Autodesk Fusion 360 part; units mm, degrees
(part 4 of 8)
sketch "Servo ear rail | adjustable, purchased fit pending | profile" plane through (0, 0, 2.8) normal (0, 0, 1) x (1, 0, 0) in component "05 | MG996R gripper cassette"
  line L0 (10, -13) -> (16.5, -13)
  line L1 (16.5, -13) -> (17, -12.5)
  line L2 (17, -12.5) -> (17, 12.5)
  line L3 (17, 12.5) -> (16.5, 13)
  line L4 (16.5, 13) -> (10, 13)
  line L5 (10, 13) -> (9.5, 12.5)
  line L6 (9.5, 12.5) -> (9.5, -12.5)
  line L7 (9.5, -12.5) -> (10, -13)
  line L8 (11, -5) -> (11.0288, -5.2926)
  line L9 (11.0288, -5.2926) -> (11.1142, -5.574)
  line L10 (11.1142, -5.574) -> (11.2528, -5.8334)
  line L11 (11.2528, -5.8334) -> (11.4393, -6.0607)
  line L12 (11.4393, -6.0607) -> (11.6666, -6.2472)
  line L13 (11.6666, -6.2472) -> (11.926, -6.3858)
  line L14 (11.926, -6.3858) -> (12.2074, -6.4712)
  line L15 (12.2074, -6.4712) -> (12.5, -6.5)
  line L16 (12.5, -6.5) -> (15, -6.5)
  line L17 (15, -6.5) -> (15.2926, -6.4712)
  line L18 (15.2926, -6.4712) -> (15.574, -6.3858)
  line L19 (15.574, -6.3858) -> (15.8334, -6.2472)
  line L20 (15.8334, -6.2472) -> (16.0607, -6.0607)
  line L21 (16.0607, -6.0607) -> (16.2472, -5.8334)
  line L22 (16.2472, -5.8334) -> (16.3858, -5.574)
  line L23 (16.3858, -5.574) -> (16.4712, -5.2926)
  line L24 (16.4712, -5.2926) -> (16.5, -5)
  line L25 (16.5, -5) -> (16.4712, -4.7074)
  line L26 (16.4712, -4.7074) -> (16.3858, -4.426)
  line L27 (16.3858, -4.426) -> (16.2472, -4.1666)
  line L28 (16.2472, -4.1666) -> (16.0607, -3.9393)
  line L29 (16.0607, -3.9393) -> (15.8334, -3.7528)
  line L30 (15.8334, -3.7528) -> (15.574, -3.6142)
  line L31 (15.574, -3.6142) -> (15.2926, -3.5288)
  line L32 (15.2926, -3.5288) -> (15, -3.5)
  line L33 (15, -3.5) -> (12.5, -3.5)
  line L34 (12.5, -3.5) -> (12.2074, -3.5288)
  line L35 (12.2074, -3.5288) -> (11.926, -3.6142)
  line L36 (11.926, -3.6142) -> (11.6666, -3.7528)
  line L37 (11.6666, -3.7528) -> (11.4393, -3.9393)
  line L38 (11.4393, -3.9393) -> (11.2528, -4.1666)
  line L39 (11.2528, -4.1666) -> (11.1142, -4.426)
  line L40 (11.1142, -4.426) -> (11.0288, -4.7074)
  line L41 (11.0288, -4.7074) -> (11, -5)
  line L42 (11, 5) -> (11.0288, 4.7074)
  line L43 (11.0288, 4.7074) -> (11.1142, 4.426)
  line L44 (11.1142, 4.426) -> (11.2528, 4.1666)
  line L45 (11.2528, 4.1666) -> (11.4393, 3.9393)
  line L46 (11.4393, 3.9393) -> (11.6666, 3.7528)
  line L47 (11.6666, 3.7528) -> (11.926, 3.6142)
  line L48 (11.926, 3.6142) -> (12.2074, 3.5288)
  line L49 (12.2074, 3.5288) -> (12.5, 3.5)
  line L50 (12.5, 3.5) -> (15, 3.5)
  line L51 (15, 3.5) -> (15.2926, 3.5288)
  line L52 (15.2926, 3.5288) -> (15.574, 3.6142)
  line L53 (15.574, 3.6142) -> (15.8334, 3.7528)
  line L54 (15.8334, 3.7528) -> (16.0607, 3.9393)
  line L55 (16.0607, 3.9393) -> (16.2472, 4.1666)
  line L56 (16.2472, 4.1666) -> (16.3858, 4.426)
  line L57 (16.3858, 4.426) -> (16.4712, 4.7074)
  line L58 (16.4712, 4.7074) -> (16.5, 5)
  line L59 (16.5, 5) -> (16.4712, 5.2926)
  line L60 (16.4712, 5.2926) -> (16.3858, 5.574)
  line L61 (16.3858, 5.574) -> (16.2472, 5.8334)
  line L62 (16.2472, 5.8334) -> (16.0607, 6.0607)
  line L63 (16.0607, 6.0607) -> (15.8334, 6.2472)
  line L64 (15.8334, 6.2472) -> (15.574, 6.3858)
  line L65 (15.574, 6.3858) -> (15.2926, 6.4712)
  line L66 (15.2926, 6.4712) -> (15, 6.5)
  line L67 (15, 6.5) -> (12.5, 6.5)
  line L68 (12.5, 6.5) -> (12.2074, 6.4712)
  line L69 (12.2074, 6.4712) -> (11.926, 6.3858)
  line L70 (11.926, 6.3858) -> (11.6666, 6.2472)
  line L71 (11.6666, 6.2472) -> (11.4393, 6.0607)
  line L72 (11.4393, 6.0607) -> (11.2528, 5.8334)
  line L73 (11.2528, 5.8334) -> (11.1142, 5.574)
  line L74 (11.1142, 5.574) -> (11.0288, 5.2926)
  line L75 (11.0288, 5.2926) -> (11, 5)
  circle A0 centre (13.25, -10) radius 1.1
  circle A1 centre (13.25, 10) radius 1.1
extrude "Servo ear rail | adjustable, purchased fit pending" add sketch "Servo ear rail | adjustable, purchased fit pending | profile" along normal blind 2.5 separate body makes body 137 in component "05 | MG996R gripper cassette"
ref_plane "WorkPlane9" through (0, 0, -22.5) normal (0, 0, 1) x (1, 0, 0) in component "05 | MG996R gripper cassette"
sketch "Servo rail support post | profile" plane through (0, 0, -22.5) normal (0, 0, 1) x (1, 0, 0) in component "05 | MG996R gripper cassette"
  circle A0 centre (13.25, -10) radius 2.5
  circle A1 centre (13.25, -10) radius 1.1
extrude "Servo rail support post" add sketch "Servo rail support post | profile" along normal blind 25.3 separate body makes body 138 in component "05 | MG996R gripper cassette"
ref_plane "WorkPlane10" through (0, 0, -22.5) normal (0, 0, 1) x (1, 0, 0) in component "05 | MG996R gripper cassette"
sketch "Servo rail support post | profile (1)" plane through (0, 0, -22.5) normal (0, 0, 1) x (1, 0, 0) in component "05 | MG996R gripper cassette"
  circle A0 centre (13.25, 10) radius 2.5
  circle A1 centre (13.25, 10) radius 1.1
extrude "Servo rail support post (1)" add sketch "Servo rail support post | profile (1)" along normal blind 25.3 separate body makes body 139 in component "05 | MG996R gripper cassette"
ref_plane "WorkPlane11" through (0, 0, 2.8) normal (0, 0, 1) x (1, 0, 0) in component "05 | MG996R gripper cassette"
sketch "Servo ear rail | adjustable, purchased fit pending | profile (1)" plane through (0, 0, 2.8) normal (0, 0, 1) x (1, 0, 0) in component "05 | MG996R gripper cassette"
  line L0 (59.5, -13) -> (66, -13)
  line L1 (66, -13) -> (66.5, -12.5)
  line L2 (66.5, -12.5) -> (66.5, 12.5)
  line L3 (66.5, 12.5) -> (66, 13)
  line L4 (66, 13) -> (59.5, 13)
  line L5 (59.5, 13) -> (59, 12.5)
  line L6 (59, 12.5) -> (59, -12.5)
  line L7 (59, -12.5) -> (59.5, -13)
  line L8 (59.5, -5) -> (59.5288, -5.2926)
  line L9 (59.5288, -5.2926) -> (59.6142, -5.574)
  line L10 (59.6142, -5.574) -> (59.7528, -5.8334)
  line L11 (59.7528, -5.8334) -> (59.9393, -6.0607)
  line L12 (59.9393, -6.0607) -> (60.1666, -6.2472)
  line L13 (60.1666, -6.2472) -> (60.426, -6.3858)
  line L14 (60.426, -6.3858) -> (60.7074, -6.4712)
  line L15 (60.7074, -6.4712) -> (61, -6.5)
  line L16 (61, -6.5) -> (63.5, -6.5)
  line L17 (63.5, -6.5) -> (63.7926, -6.4712)
  line L18 (63.7926, -6.4712) -> (64.074, -6.3858)
  line L19 (64.074, -6.3858) -> (64.3334, -6.2472)
  line L20 (64.3334, -6.2472) -> (64.5607, -6.0607)
  line L21 (64.5607, -6.0607) -> (64.7472, -5.8334)
  line L22 (64.7472, -5.8334) -> (64.8858, -5.574)
  line L23 (64.8858, -5.574) -> (64.9712, -5.2926)
  line L24 (64.9712, -5.2926) -> (65, -5)
  line L25 (65, -5) -> (64.9712, -4.7074)
  line L26 (64.9712, -4.7074) -> (64.8858, -4.426)
  line L27 (64.8858, -4.426) -> (64.7472, -4.1666)
  line L28 (64.7472, -4.1666) -> (64.5607, -3.9393)
  line L29 (64.5607, -3.9393) -> (64.3334, -3.7528)
  line L30 (64.3334, -3.7528) -> (64.074, -3.6142)
  line L31 (64.074, -3.6142) -> (63.7926, -3.5288)
  line L32 (63.7926, -3.5288) -> (63.5, -3.5)
  line L33 (63.5, -3.5) -> (61, -3.5)
  line L34 (61, -3.5) -> (60.7074, -3.5288)
  line L35 (60.7074, -3.5288) -> (60.426, -3.6142)
  line L36 (60.426, -3.6142) -> (60.1666, -3.7528)
  line L37 (60.1666, -3.7528) -> (59.9393, -3.9393)
  line L38 (59.9393, -3.9393) -> (59.7528, -4.1666)
  line L39 (59.7528, -4.1666) -> (59.6142, -4.426)
  line L40 (59.6142, -4.426) -> (59.5288, -4.7074)
  line L41 (59.5288, -4.7074) -> (59.5, -5)
  line L42 (59.5, 5) -> (59.5288, 4.7074)
  line L43 (59.5288, 4.7074) -> (59.6142, 4.426)
  line L44 (59.6142, 4.426) -> (59.7528, 4.1666)
  line L45 (59.7528, 4.1666) -> (59.9393, 3.9393)
  line L46 (59.9393, 3.9393) -> (60.1666, 3.7528)
  line L47 (60.1666, 3.7528) -> (60.426, 3.6142)
  line L48 (60.426, 3.6142) -> (60.7074, 3.5288)
  line L49 (60.7074, 3.5288) -> (61, 3.5)
  line L50 (61, 3.5) -> (63.5, 3.5)
  line L51 (63.5, 3.5) -> (63.7926, 3.5288)
  line L52 (63.7926, 3.5288) -> (64.074, 3.6142)
  line L53 (64.074, 3.6142) -> (64.3334, 3.7528)
  line L54 (64.3334, 3.7528) -> (64.5607, 3.9393)
  line L55 (64.5607, 3.9393) -> (64.7472, 4.1666)
  line L56 (64.7472, 4.1666) -> (64.8858, 4.426)
  line L57 (64.8858, 4.426) -> (64.9712, 4.7074)
  line L58 (64.9712, 4.7074) -> (65, 5)
  line L59 (65, 5) -> (64.9712, 5.2926)
  line L60 (64.9712, 5.2926) -> (64.8858, 5.574)
  line L61 (64.8858, 5.574) -> (64.7472, 5.8334)
  line L62 (64.7472, 5.8334) -> (64.5607, 6.0607)
  line L63 (64.5607, 6.0607) -> (64.3334, 6.2472)
  line L64 (64.3334, 6.2472) -> (64.074, 6.3858)
  line L65 (64.074, 6.3858) -> (63.7926, 6.4712)
  line L66 (63.7926, 6.4712) -> (63.5, 6.5)
  line L67 (63.5, 6.5) -> (61, 6.5)
  line L68 (61, 6.5) -> (60.7074, 6.4712)
  line L69 (60.7074, 6.4712) -> (60.426, 6.3858)
  line L70 (60.426, 6.3858) -> (60.1666, 6.2472)
  line L71 (60.1666, 6.2472) -> (59.9393, 6.0607)
  line L72 (59.9393, 6.0607) -> (59.7528, 5.8334)
  line L73 (59.7528, 5.8334) -> (59.6142, 5.574)
  line L74 (59.6142, 5.574) -> (59.5288, 5.2926)
  line L75 (59.5288, 5.2926) -> (59.5, 5)
  circle A0 centre (62.75, -10) radius 1.1
  circle A1 centre (62.75, 10) radius 1.1
extrude "Servo ear rail | adjustable, purchased fit pending (1)" add sketch "Servo ear rail | adjustable, purchased fit pending | profile (1)" along normal blind 2.5 separate body makes body 140 in component "05 | MG996R gripper cassette"
ref_plane "WorkPlane12" through (0, 0, -22.5) normal (0, 0, 1) x (1, 0, 0) in component "05 | MG996R gripper cassette"
sketch "Servo rail support post | profile (2)" plane through (0, 0, -22.5) normal (0, 0, 1) x (1, 0, 0) in component "05 | MG996R gripper cassette"
  circle A0 centre (62.75, -10) radius 2.5
  circle A1 centre (62.75, -10) radius 1.1
extrude "Servo rail support post (2)" add sketch "Servo rail support post | profile (2)" along normal blind 25.3 separate body makes body 141 in component "05 | MG996R gripper cassette"
ref_plane "WorkPlane13" through (0, 0, -22.5) normal (0, 0, 1) x (1, 0, 0) in component "05 | MG996R gripper cassette"
sketch "Servo rail support post | profile (3)" plane through (0, 0, -22.5) normal (0, 0, 1) x (1, 0, 0) in component "05 | MG996R gripper cassette"
  circle A0 centre (62.75, 10) radius 2.5
  circle A1 centre (62.75, 10) radius 1.1
extrude "Servo rail support post (3)" add sketch "Servo rail support post | profile (3)" along normal blind 25.3 separate body makes body 142 in component "05 | MG996R gripper cassette"
ref_plane "WorkPlane14" through (0, 0, 6) normal (0, 0, 1) x (1, 0, 0) in component "05 | MG996R gripper cassette"
sketch "Finger pivot support bridge | profile" plane through (0, 0, 6) normal (0, 0, 1) x (1, 0, 0) in component "05 | MG996R gripper cassette"
  line L0 (66, -23) -> (84, -23)
  line L1 (84, -23) -> (85, -22)
  line L2 (85, -22) -> (85, 22)
  line L3 (85, 22) -> (84, 23)
  line L4 (84, 23) -> (66, 23)
  line L5 (66, 23) -> (65, 22)
  line L6 (65, 22) -> (65, -22)
  line L7 (65, -22) -> (66, -23)
  circle A0 centre (69, -18) radius 1.1
  circle A1 centre (69, 18) radius 1.1
  circle A2 centre (81, -18) radius 1.1
  circle A3 centre (81, 18) radius 1.1
  circle A4 centre (75, -12) radius 3.05
  circle A5 centre (75, 12) radius 3.05
extrude "Finger pivot support bridge" add sketch "Finger pivot support bridge | profile" along normal blind 3 separate body makes body 143 in component "05 | MG996R gripper cassette"
ref_plane "WorkPlane15" through (0, 0, -22.5) normal (0, 0, 1) x (1, 0, 0) in component "05 | MG996R gripper cassette"
sketch "Finger pivot support post | profile" plane through (0, 0, -22.5) normal (0, 0, 1) x (1, 0, 0) in component "05 | MG996R gripper cassette"
  circle A0 centre (69, -18) radius 2.8
  circle A1 centre (69, -18) radius 1.1
extrude "Finger pivot support post" add sketch "Finger pivot support post | profile" along normal blind 28.5 separate body makes body 144 in component "05 | MG996R gripper cassette"
ref_plane "WorkPlane16" through (0, 0, -22.5) normal (0, 0, 1) x (1, 0, 0) in component "05 | MG996R gripper cassette"
sketch "Finger pivot support post | profile (1)" plane through (0, 0, -22.5) normal (0, 0, 1) x (1, 0, 0) in component "05 | MG996R gripper cassette"
  circle A0 centre (69, 18) radius 2.8
  circle A1 centre (69, 18) radius 1.1
extrude "Finger pivot support post (1)" add sketch "Finger pivot support post | profile (1)" along normal blind 28.5 separate body makes body 145 in component "05 | MG996R gripper cassette"
ref_plane "WorkPlane17" through (0, 0, -22.5) normal (0, 0, 1) x (1, 0, 0) in component "05 | MG996R gripper cassette"
sketch "Finger pivot support post | profile (2)" plane through (0, 0, -22.5) normal (0, 0, 1) x (1, 0, 0) in component "05 | MG996R gripper cassette"
  circle A0 centre (81, -18) radius 2.8
  circle A1 centre (81, -18) radius 1.1
extrude "Finger pivot support post (2)" add sketch "Finger pivot support post | profile (2)" along normal blind 28.5 separate body makes body 146 in component "05 | MG996R gripper cassette"
ref_plane "WorkPlane18" through (0, 0, -22.5) normal (0, 0, 1) x (1, 0, 0) in component "05 | MG996R gripper cassette"
sketch "Finger pivot support post | profile (3)" plane through (0, 0, -22.5) normal (0, 0, 1) x (1, 0, 0) in component "05 | MG996R gripper cassette"
  circle A0 centre (81, 18) radius 2.8
  circle A1 centre (81, 18) radius 1.1
extrude "Finger pivot support post (3)" add sketch "Finger pivot support post | profile (3)" along normal blind 28.5 separate body makes body 147 in component "05 | MG996R gripper cassette"
ref_plane "WorkPlane19" through (0, 0, 5.5) normal (0, 0, 1) x (1, 0, 0) in component "05 | MG996R gripper cassette"
sketch "Finger plain bushing | fit pending | profile" plane through (0, 0, 5.5) normal (0, 0, 1) x (1, 0, 0) in component "05 | MG996R gripper cassette"
  circle A0 centre (75, -12) radius 3
  circle A1 centre (75, -12) radius 1.55
extrude "Finger plain bushing | fit pending" add sketch "Finger plain bushing | fit pending | profile" along normal blind 4.5 separate body makes body 148 in component "05 | MG996R gripper cassette"
ref_plane "WorkPlane20" through (0, 0, 5.5) normal (0, 0, 1) x (1, 0, 0) in component "05 | MG996R gripper cassette"
sketch "Finger plain bushing | fit pending | profile (1)" plane through (0, 0, 5.5) normal (0, 0, 1) x (1, 0, 0) in component "05 | MG996R gripper cassette"
  circle A0 centre (75, 12) radius 3
  circle A1 centre (75, 12) radius 1.55
extrude "Finger plain bushing | fit pending (1)" add sketch "Finger plain bushing | fit pending | profile (1)" along normal blind 4.5 separate body makes body 149 in component "05 | MG996R gripper cassette"
ref_plane "WorkPlane21" through (0, 0, 16) normal (0, 0, 1) x (1, 0, 0) in component "05 | MG996R gripper cassette"
sketch "Straight finger -1 | profile" plane through (0, 0, 16) normal (0, 0, 1) x (1, 0, 0) in component "05 | MG996R gripper cassette"
  line L0 (72, -17) -> (78, -17)
  line L1 (78, -17) -> (110, -16)
  line L2 (110, -16) -> (116, -13)
  line L3 (116, -13) -> (116, -7)
  line L4 (116, -7) -> (110, -5)
  line L5 (110, -5) -> (78, -7)
  line L6 (78, -7) -> (72, -7)
  line L7 (72, -7) -> (72, -17)
  circle A0 centre (75, -12) radius 1.6
extrude "Straight finger -1" add sketch "Straight finger -1 | profile" along normal blind 5 separate body makes body 150 in component "05 | MG996R gripper cassette"
ref_plane "WorkPlane22" through (0, 0, 16.4) normal (0, 0, 1) x (1, 0, 0) in component "05 | MG996R gripper cassette"
sketch "Replaceable TPU gripping pad -1 | profile" plane through (0, 0, 16.4) normal (0, 0, 1) x (1, 0, 0) in component "05 | MG996R gripper cassette"
  line L0 (100.6, -7.8) -> (113.4, -7.8)
  line L1 (113.4, -7.8) -> (114, -7.2)
  line L2 (114, -7.2) -> (114, -5.8)
  line L3 (114, -5.8) -> (113.4, -5.2)
  line L4 (113.4, -5.2) -> (100.6, -5.2)
  line L5 (100.6, -5.2) -> (100, -5.8)
  line L6 (100, -5.8) -> (100, -7.2)
  line L7 (100, -7.2) -> (100.6, -7.8)
extrude "Replaceable TPU gripping pad -1" add sketch "Replaceable TPU gripping pad -1 | profile" along normal blind 4.2 separate body makes body 151 in component "05 | MG996R gripper cassette"
ref_plane "WorkPlane23" through (0, 0, 16) normal (0, 0, 1) x (1, 0, 0) in component "05 | MG996R gripper cassette"
sketch "Straight finger 1 | profile" plane through (0, 0, 16) normal (0, 0, 1) x (1, 0, 0) in component "05 | MG996R gripper cassette"
  line L0 (72, 7) -> (78, 7)
  line L1 (78, 7) -> (110, 8)
  line L2 (110, 8) -> (116, 11)
  line L3 (116, 11) -> (116, 17)
  line L4 (116, 17) -> (110, 19)
  line L5 (110, 19) -> (78, 17)
  line L6 (78, 17) -> (72, 17)
  line L7 (72, 17) -> (72, 7)
  circle A0 centre (75, 12) radius 1.6
extrude "Straight finger 1" add sketch "Straight finger 1 | profile" along normal blind 5 separate body makes body 152 in component "05 | MG996R gripper cassette"
ref_plane "WorkPlane24" through (0, 0, 16.4) normal (0, 0, 1) x (1, 0, 0) in component "05 | MG996R gripper cassette"
sketch "Replaceable TPU gripping pad 1 | profile" plane through (0, 0, 16.4) normal (0, 0, 1) x (1, 0, 0) in component "05 | MG996R gripper cassette"
  line L0 (100.6, 5.2) -> (113.4, 5.2)
  line L1 (113.4, 5.2) -> (114, 5.8)
  line L2 (114, 5.8) -> (114, 7.2)
  line L3 (114, 7.2) -> (113.4, 7.8)
  line L4 (113.4, 7.8) -> (100.6, 7.8)
  line L5 (100.6, 7.8) -> (100, 7.2)
  line L6 (100, 7.2) -> (100, 5.8)
  line L7 (100, 5.8) -> (100.6, 5.2)
extrude "Replaceable TPU gripping pad 1" add sketch "Replaceable TPU gripping pad 1 | profile" along normal blind 4.2 separate body makes body 153 in component "05 | MG996R gripper cassette"
ref_plane "WorkPlane25" through (0, 0, 31) normal (0, 0, 1) x (1, 0, 0) in component "05 | MG996R gripper cassette"
sketch "Palm service screw | profile" plane through (0, 0, 31) normal (0, 0, 1) x (1, 0, 0) in component "05 | MG996R gripper cassette"
  line L0 (-7.1813, -7.95) -> (-9, -6.9)
  line L1 (-9, -6.9) -> (-10.8187, -7.95)
  line L2 (-10.8187, -7.95) -> (-10.8187, -10.05)
  line L3 (-10.8187, -10.05) -> (-9, -11.1)
  line L4 (-9, -11.1) -> (-7.1813, -10.05)
  line L5 (-7.1813, -10.05) -> (-7.1813, -7.95)
  circle A0 centre (-9, -9) radius 0.9
extrude "Palm service screw" add sketch "Palm service screw | profile" along normal blind 1 separate body makes body 154 in component "05 | MG996R gripper cassette"
ref_plane "WorkPlane26" through (0, 0, 31) normal (0, 0, 1) x (1, 0, 0) in component "05 | MG996R gripper cassette"
sketch "Palm service screw | profile (1)" plane through (0, 0, 31) normal (0, 0, 1) x (1, 0, 0) in component "05 | MG996R gripper cassette"
  line L0 (-7.1813, 10.05) -> (-9, 11.1)
  line L1 (-9, 11.1) -> (-10.8187, 10.05)
  line L2 (-10.8187, 10.05) -> (-10.8187, 7.95)
  line L3 (-10.8187, 7.95) -> (-9, 6.9)
  line L4 (-9, 6.9) -> (-7.1813, 7.95)
  line L5 (-7.1813, 7.95) -> (-7.1813, 10.05)
  circle A0 centre (-9, 9) radius 0.9
extrude "Palm service screw (1)" add sketch "Palm service screw | profile (1)" along normal blind 1 separate body makes body 155 in component "05 | MG996R gripper cassette"
ref_plane "WorkPlane27" through (0, 0, 31) normal (0, 0, 1) x (1, 0, 0) in component "05 | MG996R gripper cassette"
sketch "Palm service screw | profile (2)" plane through (0, 0, 31) normal (0, 0, 1) x (1, 0, 0) in component "05 | MG996R gripper cassette"
  line L0 (65.8187, -20.95) -> (64, -19.9)
  line L1 (64, -19.9) -> (62.1813, -20.95)
  line L2 (62.1813, -20.95) -> (62.1813, -23.05)
  line L3 (62.1813, -23.05) -> (64, -24.1)
  line L4 (64, -24.1) -> (65.8187, -23.05)
  line L5 (65.8187, -23.05) -> (65.8187, -20.95)
  circle A0 centre (64, -22) radius 0.9
extrude "Palm service screw (2)" add sketch "Palm service screw | profile (2)" along normal blind 1 separate body makes body 156 in component "05 | MG996R gripper cassette"
ref_plane "WorkPlane28" through (0, 0, 31) normal (0, 0, 1) x (1, 0, 0) in component "05 | MG996R gripper cassette"
sketch "Palm service screw | profile (3)" plane through (0, 0, 31) normal (0, 0, 1) x (1, 0, 0) in component "05 | MG996R gripper cassette"
  line L0 (65.8187, 23.05) -> (64, 24.1)
  line L1 (64, 24.1) -> (62.1813, 23.05)
  line L2 (62.1813, 23.05) -> (62.1813, 20.95)
  line L3 (62.1813, 20.95) -> (64, 19.9)
  line L4 (64, 19.9) -> (65.8187, 20.95)
  line L5 (65.8187, 20.95) -> (65.8187, 23.05)
  circle A0 centre (64, 22) radius 0.9
extrude "Palm service screw (3)" add sketch "Palm service screw | profile (3)" along normal blind 1 separate body makes body 157 in component "05 | MG996R gripper cassette"
ref_plane "WorkPlane29" through (0, 0, 5) normal (0, 0, 1) x (1, 0, 0) in component "05 | MG996R gripper cassette"
sketch "Finger pivot shaft | profile" plane through (0, 0, 5) normal (0, 0, 1) x (1, 0, 0) in component "05 | MG996R gripper cassette"
  circle A0 centre (75, -12) radius 1.5
extrude "Finger pivot shaft" add sketch "Finger pivot shaft | profile" along normal blind 19 separate body makes body 158 in component "05 | MG996R gripper cassette"
ref_plane "WorkPlane30" through (0, 0, 11) normal (0, 0, 1) x (1, 0, 0) in component "05 | MG996R gripper cassette"
sketch "Finger gear envelope | meshing geometry pending | profile" plane through (0, 0, 11) normal (0, 0, 1) x (1, 0, 0) in component "05 | MG996R gripper cassette"
  circle A0 centre (75, -12) radius 11.6
  circle A1 centre (75, -12) radius 1.6
extrude "Finger gear envelope | meshing geometry pending" add sketch "Finger gear envelope | meshing geometry pending | profile" along normal blind 4 separate body makes body 159 in component "05 | MG996R gripper cassette"
ref_plane "WorkPlane31" through (0, 0, 5) normal (0, 0, 1) x (1, 0, 0) in component "05 | MG996R gripper cassette"
sketch "Finger pivot shaft | profile (1)" plane through (0, 0, 5) normal (0, 0, 1) x (1, 0, 0) in component "05 | MG996R gripper cassette"
  circle A0 centre (75, 12) radius 1.5
extrude "Finger pivot shaft (1)" add sketch "Finger pivot shaft | profile (1)" along normal blind 19 separate body makes body 160 in component "05 | MG996R gripper cassette"
ref_plane "WorkPlane32" through (0, 0, 11) normal (0, 0, 1) x (1, 0, 0) in component "05 | MG996R gripper cassette"
sketch "Finger gear envelope | meshing geometry pending | profile (1)" plane through (0, 0, 11) normal (0, 0, 1) x (1, 0, 0) in component "05 | MG996R gripper cassette"
  circle A0 centre (75, 12) radius 11.6
  circle A1 centre (75, 12) radius 1.6
extrude "Finger gear envelope | meshing geometry pending (1)" add sketch "Finger gear envelope | meshing geometry pending | profile (1)" along normal blind 4 separate body makes body 161 in component "05 | MG996R gripper cassette"
ref_plane "WorkPlane33" through (0, 0, 19) normal (0, 0, 1) x (1, 0, 0) in component "05 | MG996R gripper cassette"
sketch "Servo horn to pulley adapter | spline and fastener pending | profile" plane through (0, 0, 19) normal (0, 0, 1) x (1, 0, 0) in component "05 | MG996R gripper cassette"
  circle A0 centre (48.35, 0) radius 5.2
  circle A1 centre (48.35, 0) radius 3
extrude "Servo horn to pulley adapter | spline and fastener pending" add sketch "Servo horn to pulley adapter | spline and fastener pending | profile" along normal blind 3 separate body makes body 162 in component "05 | MG996R gripper cassette"
ref_plane "WorkPlane34" through (0, 0, 22) normal (0, 0, 1) x (1, 0, 0) in component "05 | MG996R gripper cassette"
sketch "20T pulley envelope | tooth profile pending | profile (5)" plane through (0, 0, 22) normal (0, 0, 1) x (1, 0, 0) in component "05 | MG996R gripper cassette"
  circle A0 centre (48.35, 0) radius 6.9662
  circle A1 centre (48.35, 0) radius 3
extrude "20T pulley envelope | tooth profile pending''''" add sketch "20T pulley envelope | tooth profile pending | profile (5)" along normal blind 4 separate body makes body 163 in component "05 | MG996R gripper cassette"
ref_plane "WorkPlane35" through (0, 0, 26) normal (0, 0, 1) x (1, 0, 0) in component "05 | MG996R gripper cassette"
sketch "20T flange | profile (5)" plane through (0, 0, 26) normal (0, 0, 1) x (1, 0, 0) in component "05 | MG996R gripper cassette"
  circle A0 centre (48.35, 0) radius 7.3662
  circle A1 centre (48.35, 0) radius 3
extrude "20T flange''''" add sketch "20T flange | profile (5)" along normal blind 0.8 separate body makes body 164 in component "05 | MG996R gripper cassette"
ref_plane "WorkPlane36" through (0, 0, 22) normal (0, 0, 1) x (1, 0, 0) in component "05 | MG996R gripper cassette"
sketch "20T pulley envelope | tooth profile pending | profile (1) (3)" plane through (0, 0, 22) normal (0, 0, 1) x (1, 0, 0) in component "05 | MG996R gripper cassette"
  circle A0 centre (75, 12) radius 6.9662
  circle A1 centre (75, 12) radius 1.5
extrude "20T pulley envelope | tooth profile pending (1)''" add sketch "20T pulley envelope | tooth profile pending | profile (1) (3)" along normal blind 4 separate body makes body 165 in component "05 | MG996R gripper cassette"
ref_plane "WorkPlane37" through (0, 0, 26) normal (0, 0, 1) x (1, 0, 0) in component "05 | MG996R gripper cassette"
sketch "20T flange | profile (1) (3)" plane through (0, 0, 26) normal (0, 0, 1) x (1, 0, 0) in component "05 | MG996R gripper cassette"
  circle A0 centre (75, 12) radius 7.3662
  circle A1 centre (75, 12) radius 1.5
extrude "20T flange (1)''" add sketch "20T flange | profile (1) (3)" along normal blind 0.8 separate body makes body 166 in component "05 | MG996R gripper cassette"
ref_plane "WorkPlane38" through (0, 0, 22) normal (0, 0, 1) x (1, 0, 0) in component "05 | MG996R gripper cassette"
sketch "Gripper servo drive | routing study span | belt length pending | profile" plane through (0, 0, 22) normal (0, 0, 1) x (1, 0, 0) in component "05 | MG996R gripper cassette"
  line L0 (45.4693, 6.3975) -> (72.1193, 18.3975)
  line L1 (72.1193, 18.3975) -> (72.6531, 17.2122)
  line L2 (72.6531, 17.2122) -> (46.0031, 5.2122)
  line L3 (46.0031, 5.2122) -> (45.4693, 6.3975)
extrude "Gripper servo drive | routing study span | belt length pending" add sketch "Gripper servo drive | routing study span | belt length pending | profile" along normal blind 4 separate body makes body 167 in component "05 | MG996R gripper cassette"
ref_plane "WorkPlane39" through (0, 0, 22) normal (0, 0, 1) x (1, 0, 0) in component "05 | MG996R gripper cassette"
sketch "Gripper servo drive | routing study span | belt length pending | profile (1)" plane through (0, 0, 22) normal (0, 0, 1) x (1, 0, 0) in component "05 | MG996R gripper cassette"
  line L0 (50.6969, -5.2122) -> (77.3469, 6.7878)
  line L1 (77.3469, 6.7878) -> (77.8807, 5.6025)
  line L2 (77.8807, 5.6025) -> (51.2307, -6.3975)
  line L3 (51.2307, -6.3975) -> (50.6969, -5.2122)
extrude "Gripper servo drive | routing study span | belt length pending (1)" add sketch "Gripper servo drive | routing study span | belt length pending | profile (1)" along normal blind 4 separate body makes body 168 in component "05 | MG996R gripper cassette"
ref_plane "WorkPlane40" through (0, 0, 22) normal (0, 0, 1) x (1, 0, 0) in component "05 | MG996R gripper cassette"
sketch "Gripper servo drive | routing study drive wrap | profile" plane through (0, 0, 22) normal (0, 0, 1) x (1, 0, 0) in component "05 | MG996R gripper cassette"
  circle A0 centre (48.35, 0) radius 7.0162
  circle A1 centre (48.35, 0) radius 5.7162
extrude "Gripper servo drive | routing study drive wrap" add sketch "Gripper servo drive | routing study drive wrap | profile" along normal blind 4 separate body makes body 169 in component "05 | MG996R gripper cassette"
ref_plane "WorkPlane41" through (0, 0, 22) normal (0, 0, 1) x (1, 0, 0) in component "05 | MG996R gripper cassette"
sketch "Gripper servo drive | routing study driven wrap | profile" plane through (0, 0, 22) normal (0, 0, 1) x (1, 0, 0) in component "05 | MG996R gripper cassette"
  circle A0 centre (75, 12) radius 7.0162
  circle A1 centre (75, 12) radius 5.7162
extrude "Gripper servo drive | routing study driven wrap" add sketch "Gripper servo drive | routing study driven wrap | profile" along normal blind 4 separate body makes body 170 in component "05 | MG996R gripper cassette"
ref_plane "WorkPlane1" through (0, 0, -33) normal (0, 0, 1) x (1, 0, 0) in component "J1 | NEMA17 drawing reference"
sketch "Stator casing | nominal drawing | profile" plane through (0, 0, -33) normal (0, 0, 1) x (1, 0, 0) in component "J1 | NEMA17 drawing reference"
  line L0 (-18.15, -21.15) -> (18.15, -21.15)
  line L1 (18.15, -21.15) -> (21.15, -18.15)
  line L2 (21.15, -18.15) -> (21.15, 18.15)
  line L3 (21.15, 18.15) -> (18.15, 21.15)
  line L4 (18.15, 21.15) -> (-18.15, 21.15)
  line L5 (-18.15, 21.15) -> (-21.15, 18.15)
  line L6 (-21.15, 18.15) -> (-21.15, -18.15)
  line L7 (-21.15, -18.15) -> (-18.15, -21.15)
extrude "Stator casing | nominal drawing" add sketch "Stator casing | nominal drawing | profile" along normal blind 28 separate body makes body 171 in component "J1 | NEMA17 drawing reference"
ref_plane "WorkPlane2" through (0, 0, -40) normal (0, 0, 1) x (1, 0, 0) in component "J1 | NEMA17 drawing reference"
sketch "Rear end bell | profile" plane through (0, 0, -40) normal (0, 0, 1) x (1, 0, 0) in component "J1 | NEMA17 drawing reference"
  line L0 (-18.15, -21.15) -> (18.15, -21.15)
  line L1 (18.15, -21.15) -> (21.15, -18.15)
  line L2 (21.15, -18.15) -> (21.15, 18.15)
  line L3 (21.15, 18.15) -> (18.15, 21.15)
  line L4 (18.15, 21.15) -> (-18.15, 21.15)
  line L5 (-18.15, 21.15) -> (-21.15, 18.15)
  line L6 (-21.15, 18.15) -> (-21.15, -18.15)
  line L7 (-21.15, -18.15) -> (-18.15, -21.15)
extrude "Rear end bell" add sketch "Rear end bell | profile" along normal blind 7 separate body makes body 172 in component "J1 | NEMA17 drawing reference"
ref_plane "WorkPlane3" through (0, 0, -5) normal (0, 0, 1) x (1, 0, 0) in component "J1 | NEMA17 drawing reference"
sketch "Front mounting flange | profile" plane through (0, 0, -5) normal (0, 0, 1) x (1, 0, 0) in component "J1 | NEMA17 drawing reference"
  line L0 (-18.15, -21.15) -> (18.15, -21.15)
  line L1 (18.15, -21.15) -> (21.15, -18.15)
  line L2 (21.15, -18.15) -> (21.15, 18.15)
  line L3 (21.15, 18.15) -> (18.15, 21.15)
  line L4 (18.15, 21.15) -> (-18.15, 21.15)
  line L5 (-18.15, 21.15) -> (-21.15, 18.15)
  line L6 (-21.15, 18.15) -> (-21.15, -18.15)
  line L7 (-21.15, -18.15) -> (-18.15, -21.15)
  circle A0 centre (-15.5, -15.5) radius 1.5
  circle A1 centre (-15.5, 15.5) radius 1.5
  circle A2 centre (15.5, -15.5) radius 1.5
  circle A3 centre (15.5, 15.5) radius 1.5
extrude "Front mounting flange" add sketch "Front mounting flange | profile" along normal blind 5 separate body makes body 173 in component "J1 | NEMA17 drawing reference"
sketch "Pilot boss | profile" plane through (0, 0, 0) normal (0, 0, 1) x (1, 0, 0) in component "J1 | NEMA17 drawing reference"
  circle A0 centre (0, 0) radius 11
extrude "Pilot boss" add sketch "Pilot boss | profile" along normal blind 2 separate body makes body 174 in component "J1 | NEMA17 drawing reference"
ref_plane "WorkPlane4" through (0, 0, 2) normal (0, 0, 1) x (1, 0, 0) in component "J1 | NEMA17 drawing reference"
sketch "D output shaft | protrusion from mounting face | profile" plane through (0, 0, 2) normal (0, 0, 1) x (1, 0, 0) in component "J1 | NEMA17 drawing reference"
  line L0 (-2.5, 0) -> (-2.4786, -0.3263)
  line L1 (-2.4786, -0.3263) -> (-2.4148, -0.647)
  line L2 (-2.4148, -0.647) -> (-2.3097, -0.9567)
  line L3 (-2.3097, -0.9567) -> (-2.1651, -1.25)
  line L4 (-2.1651, -1.25) -> (-1.9834, -1.5219)
  line L5 (-1.9834, -1.5219) -> (-1.7678, -1.7678)
  line L6 (-1.7678, -1.7678) -> (-1.5219, -1.9834)
  line L7 (-1.5219, -1.9834) -> (-1.25, -2.1651)
  line L8 (-1.25, -2.1651) -> (-0.9567, -2.3097)
  line L9 (-0.9567, -2.3097) -> (-0.647, -2.4148)
  line L10 (-0.647, -2.4148) -> (-0.3263, -2.4786)
  line L11 (-0.3263, -2.4786) -> (0, -2.5)
  line L12 (0, -2.5) -> (0.3263, -2.4786)
  line L13 (0.3263, -2.4786) -> (0.647, -2.4148)
  line L14 (0.647, -2.4148) -> (0.9567, -2.3097)
  line L15 (0.9567, -2.3097) -> (1.25, -2.1651)
  line L16 (1.25, -2.1651) -> (1.5219, -1.9834)
  line L17 (1.5219, -1.9834) -> (1.7678, -1.7678)
  line L18 (1.7678, -1.7678) -> (1.9834, -1.5219)
  line L19 (1.9834, -1.5219) -> (2, -1.25)
  line L20 (2, -1.25) -> (2, 1.25)
  line L21 (2, 1.25) -> (1.9834, 1.5219)
  line L22 (1.9834, 1.5219) -> (1.7678, 1.7678)
  line L23 (1.7678, 1.7678) -> (1.5219, 1.9834)
  line L24 (1.5219, 1.9834) -> (1.25, 2.1651)
  line L25 (1.25, 2.1651) -> (0.9567, 2.3097)
  line L26 (0.9567, 2.3097) -> (0.647, 2.4148)
  line L27 (0.647, 2.4148) -> (0.3263, 2.4786)
  line L28 (0.3263, 2.4786) -> (0, 2.5)
  line L29 (0, 2.5) -> (-0.3263, 2.4786)
  line L30 (-0.3263, 2.4786) -> (-0.647, 2.4148)
  line L31 (-0.647, 2.4148) -> (-0.9567, 2.3097)
  line L32 (-0.9567, 2.3097) -> (-1.25, 2.1651)
  line L33 (-1.25, 2.1651) -> (-1.5219, 1.9834)
  line L34 (-1.5219, 1.9834) -> (-1.7678, 1.7678)
  line L35 (-1.7678, 1.7678) -> (-1.9834, 1.5219)
  line L36 (-1.9834, 1.5219) -> (-2.1651, 1.25)
  line L37 (-2.1651, 1.25) -> (-2.3097, 0.9567)
  line L38 (-2.3097, 0.9567) -> (-2.4148, 0.647)
  line L39 (-2.4148, 0.647) -> (-2.4786, 0.3263)
  line L40 (-2.4786, 0.3263) -> (-2.5, 0)
extrude "D output shaft | protrusion from mounting face" add sketch "D output shaft | protrusion from mounting face | profile" along normal blind 21 separate body makes body 175 in component "J1 | NEMA17 drawing reference"
ref_plane "WorkPlane5" through (0, 0, -39) normal (0, 0, 1) x (1, 0, 0) in component "J1 | NEMA17 drawing reference"
sketch "Cable connector | profile" plane through (0, 0, -39) normal (0, 0, 1) x (1, 0, 0) in component "J1 | NEMA17 drawing reference"
  line L0 (-5.2, -24.65) -> (5.2, -24.65)
  line L1 (5.2, -24.65) -> (6, -23.85)
  line L2 (6, -23.85) -> (6, -20.45)
  line L3 (6, -20.45) -> (5.2, -19.65)
  line L4 (5.2, -19.65) -> (-5.2, -19.65)
  line L5 (-5.2, -19.65) -> (-6, -20.45)
  line L6 (-6, -20.45) -> (-6, -23.85)
  line L7 (-6, -23.85) -> (-5.2, -24.65)
extrude "Cable connector" add sketch "Cable connector | profile" along normal blind 8 separate body makes body 176 in component "J1 | NEMA17 drawing reference"
ref_plane "WorkPlane1" through (0, 0, -69.5) normal (0, 0, 1) x (1, 0, 0) in component "J2 | NEMA23 drawing reference"
sketch "Stator casing | nominal drawing | profile (2)" plane through (0, 0, -69.5) normal (0, 0, 1) x (1, 0, 0) in component "J2 | NEMA23 drawing reference"
  line L0 (-24.5, -28.5) -> (24.5, -28.5)
  line L1 (24.5, -28.5) -> (28.5, -24.5)
  line L2 (28.5, -24.5) -> (28.5, 24.5)
  line L3 (28.5, 24.5) -> (24.5, 28.5)
  line L4 (24.5, 28.5) -> (-24.5, 28.5)
  line L5 (-24.5, 28.5) -> (-28.5, 24.5)
  line L6 (-28.5, 24.5) -> (-28.5, -24.5)
  line L7 (-28.5, -24.5) -> (-24.5, -28.5)
extrude "Stator casing | nominal drawing'" add sketch "Stator casing | nominal drawing | profile (2)" along normal blind 64.5 separate body makes body 177 in component "J2 | NEMA23 drawing reference"
ref_plane "WorkPlane2" through (0, 0, -76.5) normal (0, 0, 1) x (1, 0, 0) in component "J2 | NEMA23 drawing reference"
sketch "Rear end bell | profile (2)" plane through (0, 0, -76.5) normal (0, 0, 1) x (1, 0, 0) in component "J2 | NEMA23 drawing reference"
  line L0 (-24.5, -28.5) -> (24.5, -28.5)
  line L1 (24.5, -28.5) -> (28.5, -24.5)
  line L2 (28.5, -24.5) -> (28.5, 24.5)
  line L3 (28.5, 24.5) -> (24.5, 28.5)
  line L4 (24.5, 28.5) -> (-24.5, 28.5)
  line L5 (-24.5, 28.5) -> (-28.5, 24.5)
  line L6 (-28.5, 24.5) -> (-28.5, -24.5)
  line L7 (-28.5, -24.5) -> (-24.5, -28.5)
extrude "Rear end bell'" add sketch "Rear end bell | profile (2)" along normal blind 7 separate body makes body 178 in component "J2 | NEMA23 drawing reference"
ref_plane "WorkPlane3" through (0, 0, -5) normal (0, 0, 1) x (1, 0, 0) in component "J2 | NEMA23 drawing reference"
sketch "Front mounting flange | profile (2)" plane through (0, 0, -5) normal (0, 0, 1) x (1, 0, 0) in component "J2 | NEMA23 drawing reference"
  line L0 (-24.5, -28.5) -> (24.5, -28.5)
  line L1 (24.5, -28.5) -> (28.5, -24.5)
  line L2 (28.5, -24.5) -> (28.5, 24.5)
  line L3 (28.5, 24.5) -> (24.5, 28.5)
  line L4 (24.5, 28.5) -> (-24.5, 28.5)
  line L5 (-24.5, 28.5) -> (-28.5, 24.5)
  line L6 (-28.5, 24.5) -> (-28.5, -24.5)
  line L7 (-28.5, -24.5) -> (-24.5, -28.5)
  circle A0 centre (-23.57, -23.57) radius 2.55
  circle A1 centre (-23.57, 23.57) radius 2.55
  circle A2 centre (23.57, -23.57) radius 2.55
  circle A3 centre (23.57, 23.57) radius 2.55
extrude "Front mounting flange'" add sketch "Front mounting flange | profile (2)" along normal blind 5 separate body makes body 179 in component "J2 | NEMA23 drawing reference"
sketch "Pilot boss | profile (2)" plane through (0, 0, 0) normal (0, 0, 1) x (1, 0, 0) in component "J2 | NEMA23 drawing reference"
  circle A0 centre (0, 0) radius 19.05
extrude "Pilot boss'" add sketch "Pilot boss | profile (2)" along normal blind 2 separate body makes body 180 in component "J2 | NEMA23 drawing reference"
ref_plane "WorkPlane4" through (0, 0, 2) normal (0, 0, 1) x (1, 0, 0) in component "J2 | NEMA23 drawing reference"
sketch "D output shaft | protrusion from mounting face | profile (2)" plane through (0, 0, 2) normal (0, 0, 1) x (1, 0, 0) in component "J2 | NEMA23 drawing reference"
  line L0 (-3.175, 0) -> (-3.1478, -0.4144)
  line L1 (-3.1478, -0.4144) -> (-3.0668, -0.8218)
  line L2 (-3.0668, -0.8218) -> (-2.9333, -1.215)
  line L3 (-2.9333, -1.215) -> (-2.7496, -1.5875)
  line L4 (-2.7496, -1.5875) -> (-2.5189, -1.9328)
  line L5 (-2.5189, -1.9328) -> (-2.2451, -2.2451)
  line L6 (-2.2451, -2.2451) -> (-1.9328, -2.5189)
  line L7 (-1.9328, -2.5189) -> (-1.5875, -2.7496)
  line L8 (-1.5875, -2.7496) -> (-1.215, -2.9333)
  line L9 (-1.215, -2.9333) -> (-0.8218, -3.0668)
  line L10 (-0.8218, -3.0668) -> (-0.4144, -3.1478)
  line L11 (-0.4144, -3.1478) -> (0, -3.175)
  line L12 (0, -3.175) -> (0.4144, -3.1478)
  line L13 (0.4144, -3.1478) -> (0.8218, -3.0668)
  line L14 (0.8218, -3.0668) -> (1.215, -2.9333)
  line L15 (1.215, -2.9333) -> (1.5875, -2.7496)
  line L16 (1.5875, -2.7496) -> (1.9328, -2.5189)
  line L17 (1.9328, -2.5189) -> (2.2451, -2.2451)
  line L18 (2.2451, -2.2451) -> (2.5189, -1.9328)
  line L19 (2.5189, -1.9328) -> (2.675, -1.5875)
  line L20 (2.675, -1.5875) -> (2.675, 1.5875)
  line L21 (2.675, 1.5875) -> (2.5189, 1.9328)
  line L22 (2.5189, 1.9328) -> (2.2451, 2.2451)
  line L23 (2.2451, 2.2451) -> (1.9328, 2.5189)
  line L24 (1.9328, 2.5189) -> (1.5875, 2.7496)
  line L25 (1.5875, 2.7496) -> (1.215, 2.9333)
  line L26 (1.215, 2.9333) -> (0.8218, 3.0668)
  line L27 (0.8218, 3.0668) -> (0.4144, 3.1478)
  line L28 (0.4144, 3.1478) -> (0, 3.175)
  line L29 (0, 3.175) -> (-0.4144, 3.1478)
  line L30 (-0.4144, 3.1478) -> (-0.8218, 3.0668)
  line L31 (-0.8218, 3.0668) -> (-1.215, 2.9333)
  line L32 (-1.215, 2.9333) -> (-1.5875, 2.7496)
  line L33 (-1.5875, 2.7496) -> (-1.9328, 2.5189)
  line L34 (-1.9328, 2.5189) -> (-2.2451, 2.2451)
  line L35 (-2.2451, 2.2451) -> (-2.5189, 1.9328)
  line L36 (-2.5189, 1.9328) -> (-2.7496, 1.5875)
  line L37 (-2.7496, 1.5875) -> (-2.9333, 1.215)
  line L38 (-2.9333, 1.215) -> (-3.0668, 0.8218)
  line L39 (-3.0668, 0.8218) -> (-3.1478, 0.4144)
  line L40 (-3.1478, 0.4144) -> (-3.175, 0)
extrude "D output shaft | protrusion from mounting face'" add sketch "D output shaft | protrusion from mounting face | profile (2)" along normal blind 19 separate body makes body 181 in component "J2 | NEMA23 drawing reference"
ref_plane "WorkPlane5" through (0, 0, -75.5) normal (0, 0, 1) x (1, 0, 0) in component "J2 | NEMA23 drawing reference"
sketch "Cable connector | profile (2)" plane through (0, 0, -75.5) normal (0, 0, 1) x (1, 0, 0) in component "J2 | NEMA23 drawing reference"
  line L0 (-5.2, -32) -> (5.2, -32)
  line L1 (5.2, -32) -> (6, -31.2)
  line L2 (6, -31.2) -> (6, -27.8)
  line L3 (6, -27.8) -> (5.2, -27)
  line L4 (5.2, -27) -> (-5.2, -27)
  line L5 (-5.2, -27) -> (-6, -27.8)
  line L6 (-6, -27.8) -> (-6, -31.2)
  line L7 (-6, -31.2) -> (-5.2, -32)
extrude "Cable connector'" add sketch "Cable connector | profile (2)" along normal blind 8 separate body makes body 182 in component "J2 | NEMA23 drawing reference"
ref_plane "WorkPlane1" through (0, 0, -33) normal (0, 0, 1) x (1, 0, 0) in component "J3 | NEMA17 drawing reference"
sketch "Stator casing | nominal drawing | profile (3)" plane through (0, 0, -33) normal (0, 0, 1) x (1, 0, 0) in component "J3 | NEMA17 drawing reference"
  line L0 (-18.15, -21.15) -> (18.15, -21.15)
  line L1 (18.15, -21.15) -> (21.15, -18.15)
  line L2 (21.15, -18.15) -> (21.15, 18.15)
  line L3 (21.15, 18.15) -> (18.15, 21.15)
  line L4 (18.15, 21.15) -> (-18.15, 21.15)
  line L5 (-18.15, 21.15) -> (-21.15, 18.15)
  line L6 (-21.15, 18.15) -> (-21.15, -18.15)
  line L7 (-21.15, -18.15) -> (-18.15, -21.15)
extrude "Stator casing | nominal drawing''" add sketch "Stator casing | nominal drawing | profile (3)" along normal blind 28 separate body makes body 183 in component "J3 | NEMA17 drawing reference"
ref_plane "WorkPlane2" through (0, 0, -40) normal (0, 0, 1) x (1, 0, 0) in component "J3 | NEMA17 drawing reference"
sketch "Rear end bell | profile (3)" plane through (0, 0, -40) normal (0, 0, 1) x (1, 0, 0) in component "J3 | NEMA17 drawing reference"
  line L0 (-18.15, -21.15) -> (18.15, -21.15)
  line L1 (18.15, -21.15) -> (21.15, -18.15)
  line L2 (21.15, -18.15) -> (21.15, 18.15)
  line L3 (21.15, 18.15) -> (18.15, 21.15)
  line L4 (18.15, 21.15) -> (-18.15, 21.15)
  line L5 (-18.15, 21.15) -> (-21.15, 18.15)
  line L6 (-21.15, 18.15) -> (-21.15, -18.15)
  line L7 (-21.15, -18.15) -> (-18.15, -21.15)
extrude "Rear end bell''" add sketch "Rear end bell | profile (3)" along normal blind 7 separate body makes body 184 in component "J3 | NEMA17 drawing reference"
ref_plane "WorkPlane3" through (0, 0, -5) normal (0, 0, 1) x (1, 0, 0) in component "J3 | NEMA17 drawing reference"
sketch "Front mounting flange | profile (3)" plane through (0, 0, -5) normal (0, 0, 1) x (1, 0, 0) in component "J3 | NEMA17 drawing reference"
  line L0 (-18.15, -21.15) -> (18.15, -21.15)
  line L1 (18.15, -21.15) -> (21.15, -18.15)
  line L2 (21.15, -18.15) -> (21.15, 18.15)
  line L3 (21.15, 18.15) -> (18.15, 21.15)
  line L4 (18.15, 21.15) -> (-18.15, 21.15)
  line L5 (-18.15, 21.15) -> (-21.15, 18.15)
  line L6 (-21.15, 18.15) -> (-21.15, -18.15)
  line L7 (-21.15, -18.15) -> (-18.15, -21.15)
  circle A0 centre (-15.5, -15.5) radius 1.5
  circle A1 centre (-15.5, 15.5) radius 1.5
  circle A2 centre (15.5, -15.5) radius 1.5
  circle A3 centre (15.5, 15.5) radius 1.5
extrude "Front mounting flange''" add sketch "Front mounting flange | profile (3)" along normal blind 5 separate body makes body 185 in component "J3 | NEMA17 drawing reference"
sketch "Pilot boss | profile (3)" plane through (0, 0, 0) normal (0, 0, 1) x (1, 0, 0) in component "J3 | NEMA17 drawing reference"
  circle A0 centre (0, 0) radius 11
extrude "Pilot boss''" add sketch "Pilot boss | profile (3)" along normal blind 2 separate body makes body 186 in component "J3 | NEMA17 drawing reference"
ref_plane "WorkPlane4" through (0, 0, 2) normal (0, 0, 1) x (1, 0, 0) in component "J3 | NEMA17 drawing reference"
sketch "D output shaft | protrusion from mounting face | profile (3)" plane through (0, 0, 2) normal (0, 0, 1) x (1, 0, 0) in component "J3 | NEMA17 drawing reference"
  line L0 (-2.5, 0) -> (-2.4786, -0.3263)
  line L1 (-2.4786, -0.3263) -> (-2.4148, -0.647)
  line L2 (-2.4148, -0.647) -> (-2.3097, -0.9567)
  line L3 (-2.3097, -0.9567) -> (-2.1651, -1.25)
  line L4 (-2.1651, -1.25) -> (-1.9834, -1.5219)
  line L5 (-1.9834, -1.5219) -> (-1.7678, -1.7678)
  line L6 (-1.7678, -1.7678) -> (-1.5219, -1.9834)
  line L7 (-1.5219, -1.9834) -> (-1.25, -2.1651)
  line L8 (-1.25, -2.1651) -> (-0.9567, -2.3097)
  line L9 (-0.9567, -2.3097) -> (-0.647, -2.4148)
  line L10 (-0.647, -2.4148) -> (-0.3263, -2.4786)
  line L11 (-0.3263, -2.4786) -> (0, -2.5)
  line L12 (0, -2.5) -> (0.3263, -2.4786)
  line L13 (0.3263, -2.4786) -> (0.647, -2.4148)
  line L14 (0.647, -2.4148) -> (0.9567, -2.3097)
  line L15 (0.9567, -2.3097) -> (1.25, -2.1651)
  line L16 (1.25, -2.1651) -> (1.5219, -1.9834)
  line L17 (1.5219, -1.9834) -> (1.7678, -1.7678)
  line L18 (1.7678, -1.7678) -> (1.9834, -1.5219)
  line L19 (1.9834, -1.5219) -> (2, -1.25)
  line L20 (2, -1.25) -> (2, 1.25)
  line L21 (2, 1.25) -> (1.9834, 1.5219)
  line L22 (1.9834, 1.5219) -> (1.7678, 1.7678)
  line L23 (1.7678, 1.7678) -> (1.5219, 1.9834)
  line L24 (1.5219, 1.9834) -> (1.25, 2.1651)
  line L25 (1.25, 2.1651) -> (0.9567, 2.3097)
  line L26 (0.9567, 2.3097) -> (0.647, 2.4148)
  line L27 (0.647, 2.4148) -> (0.3263, 2.4786)
  line L28 (0.3263, 2.4786) -> (0, 2.5)
  line L29 (0, 2.5) -> (-0.3263, 2.4786)
  line L30 (-0.3263, 2.4786) -> (-0.647, 2.4148)
  line L31 (-0.647, 2.4148) -> (-0.9567, 2.3097)
  line L32 (-0.9567, 2.3097) -> (-1.25, 2.1651)
  line L33 (-1.25, 2.1651) -> (-1.5219, 1.9834)
  line L34 (-1.5219, 1.9834) -> (-1.7678, 1.7678)
  line L35 (-1.7678, 1.7678) -> (-1.9834, 1.5219)
  line L36 (-1.9834, 1.5219) -> (-2.1651, 1.25)
  line L37 (-2.1651, 1.25) -> (-2.3097, 0.9567)
  line L38 (-2.3097, 0.9567) -> (-2.4148, 0.647)
  line L39 (-2.4148, 0.647) -> (-2.4786, 0.3263)
  line L40 (-2.4786, 0.3263) -> (-2.5, 0)
extrude "D output shaft | protrusion from mounting face''" add sketch "D output shaft | protrusion from mounting face | profile (3)" along normal blind 21 separate body makes body 187 in component "J3 | NEMA17 drawing reference"
ref_plane "WorkPlane5" through (0, 0, -39) normal (0, 0, 1) x (1, 0, 0) in component "J3 | NEMA17 drawing reference"
sketch "Cable connector | profile (3)" plane through (0, 0, -39) normal (0, 0, 1) x (1, 0, 0) in component "J3 | NEMA17 drawing reference"
  line L0 (-5.2, -24.65) -> (5.2, -24.65)
  line L1 (5.2, -24.65) -> (6, -23.85)
  line L2 (6, -23.85) -> (6, -20.45)
  line L3 (6, -20.45) -> (5.2, -19.65)
  line L4 (5.2, -19.65) -> (-5.2, -19.65)
  line L5 (-5.2, -19.65) -> (-6, -20.45)
  line L6 (-6, -20.45) -> (-6, -23.85)
  line L7 (-6, -23.85) -> (-5.2, -24.65)
extrude "Cable connector''" add sketch "Cable connector | profile (3)" along normal blind 8 separate body makes body 188 in component "J3 | NEMA17 drawing reference"
ref_plane "WorkPlane1" through (0, 0, -33) normal (0, 0, 1) x (1, 0, 0) in component "J4 | NEMA17 drawing reference"
sketch "Stator casing | nominal drawing | profile (4)" plane through (0, 0, -33) normal (0, 0, 1) x (1, 0, 0) in component "J4 | NEMA17 drawing reference"
  line L0 (-18.15, -21.15) -> (18.15, -21.15)
  line L1 (18.15, -21.15) -> (21.15, -18.15)
  line L2 (21.15, -18.15) -> (21.15, 18.15)
  line L3 (21.15, 18.15) -> (18.15, 21.15)
  line L4 (18.15, 21.15) -> (-18.15, 21.15)
  line L5 (-18.15, 21.15) -> (-21.15, 18.15)
  line L6 (-21.15, 18.15) -> (-21.15, -18.15)
  line L7 (-21.15, -18.15) -> (-18.15, -21.15)
extrude "Stator casing | nominal drawing'''" add sketch "Stator casing | nominal drawing | profile (4)" along normal blind 28 separate body makes body 189 in component "J4 | NEMA17 drawing reference"
ref_plane "WorkPlane2" through (0, 0, -40) normal (0, 0, 1) x (1, 0, 0) in component "J4 | NEMA17 drawing reference"
sketch "Rear end bell | profile (4)" plane through (0, 0, -40) normal (0, 0, 1) x (1, 0, 0) in component "J4 | NEMA17 drawing reference"
  line L0 (-18.15, -21.15) -> (18.15, -21.15)
  line L1 (18.15, -21.15) -> (21.15, -18.15)
  line L2 (21.15, -18.15) -> (21.15, 18.15)
  line L3 (21.15, 18.15) -> (18.15, 21.15)
  line L4 (18.15, 21.15) -> (-18.15, 21.15)
  line L5 (-18.15, 21.15) -> (-21.15, 18.15)
  line L6 (-21.15, 18.15) -> (-21.15, -18.15)
  line L7 (-21.15, -18.15) -> (-18.15, -21.15)
extrude "Rear end bell'''" add sketch "Rear end bell | profile (4)" along normal blind 7 separate body makes body 190 in component "J4 | NEMA17 drawing reference"
ref_plane "WorkPlane3" through (0, 0, -5) normal (0, 0, 1) x (1, 0, 0) in component "J4 | NEMA17 drawing reference"
sketch "Front mounting flange | profile (4)" plane through (0, 0, -5) normal (0, 0, 1) x (1, 0, 0) in component "J4 | NEMA17 drawing reference"
  line L0 (-18.15, -21.15) -> (18.15, -21.15)
  line L1 (18.15, -21.15) -> (21.15, -18.15)
  line L2 (21.15, -18.15) -> (21.15, 18.15)
  line L3 (21.15, 18.15) -> (18.15, 21.15)
  line L4 (18.15, 21.15) -> (-18.15, 21.15)
  line L5 (-18.15, 21.15) -> (-21.15, 18.15)
  line L6 (-21.15, 18.15) -> (-21.15, -18.15)
  line L7 (-21.15, -18.15) -> (-18.15, -21.15)
  circle A0 centre (-15.5, -15.5) radius 1.5
  circle A1 centre (-15.5, 15.5) radius 1.5
  circle A2 centre (15.5, -15.5) radius 1.5
  circle A3 centre (15.5, 15.5) radius 1.5
extrude "Front mounting flange'''" add sketch "Front mounting flange | profile (4)" along normal blind 5 separate body makes body 191 in component "J4 | NEMA17 drawing reference"
sketch "Pilot boss | profile (4)" plane through (0, 0, 0) normal (0, 0, 1) x (1, 0, 0) in component "J4 | NEMA17 drawing reference"
  circle A0 centre (0, 0) radius 11
extrude "Pilot boss'''" add sketch "Pilot boss | profile (4)" along normal blind 2 separate body makes body 192 in component "J4 | NEMA17 drawing reference"
ref_plane "WorkPlane4" through (0, 0, 2) normal (0, 0, 1) x (1, 0, 0) in component "J4 | NEMA17 drawing reference"